v100-straight-blower-duct (Autodesk Fusion 360 design; units mm, degrees)
Autodesk Fusion 360 part; units mm, degrees
sketch "Sketch194" plane through (0, 0, 0) normal (0, 0, 1) x (1, 0, 0)
  line L0 (6.21, -2.88) -> (5.01, -5.52)
  line L1 (5.01, -5.52) -> (2.97, -16.54)
  line L2 (2.97, -16.54) -> (3.01, -81.43)
  line L3 (3.01, -81.43) -> (5.44, -92.47)
  line L4 (5.44, -92.47) -> (7.01, -95.15)
  line L5 (7.01, -95.15) -> (10.23, -96.74)
  line L6 (10.23, -96.74) -> (25.5, -96.54)
  line L7 (25.5, -96.54) -> (30.03, -93.08)
  line L8 (30.03, -93.08) -> (35.46, -92.81)
  line L9 (35.46, -92.81) -> (36.19, -92.08)
  line L10 (36.19, -92.08) -> (36.46, -90.79)
  line L11 (36.46, -90.79) -> (36.46, -41.42)
  line L12 (36.46, -41.42) -> (36.19, -40.42)
  line L13 (36.19, -40.42) -> (35.46, -39.68)
  line L14 (35.46, -39.68) -> (34.46, -39.42)
  line L15 (34.46, -39.42) -> (23.59, -39.42)
  line L16 (23.59, -39.42) -> (23.59, -19.42)
  line L17 (23.59, -19.42) -> (31.82, -19.22)
  line L18 (31.82, -19.22) -> (32.12, -16.44)
  line L19 (32.12, -16.44) -> (31.86, -6.46)
  line L20 (31.86, -6.46) -> (24.9, -0.57)
  line L21 (24.9, -0.57) -> (9.15, -0.57)
  line L22 (9.15, -0.57) -> (6.21, -2.88)
extrude "Extrude154" add sketch "Sketch194" along normal blind 3 makes body 1
ref_plane "WorkPlane174" through (0, 0, 3) normal (0, 0, 1) x (1, 0, 0)
sketch "Sketch195" plane through (0, 0, 3) normal (0, 0, 1) x (1, 0, 0)
  line L0 (6.78, -93) -> (28.42, -93)
  line L1 (28.42, -93) -> (28.42, -4.34)
  line L2 (28.42, -4.34) -> (6.78, -4.34)
  line L3 (6.78, -4.34) -> (6.78, -93)
ref_plane "WorkPlane175" through (0, 0, 20) normal (0, 0, 1) x (1, 0, 0)
sketch "Sketch196" plane through (0, 0, 20) normal (0, 0, 1) x (1, 0, 0)
  line L0 (4.3, -102.1) -> (29.9, -102.1)
  line L1 (29.9, -102.1) -> (29.9, 5.5)
  line L2 (29.9, 5.5) -> (4.3, 5.5)
  line L3 (4.3, 5.5) -> (4.3, -102.1)
loft "Loft21" add profiles "Sketch195", "Sketch196" section 1 section 2 separate body makes body 2
ref_plane "WorkPlane176" through (0, 0, 20) normal (0, 0, 1) x (1, 0, 0)
sketch "Sketch197" plane through (0, 0, 20) normal (0, 0, 1) x (1, 0, 0)
  line L0 (0, -104.4) -> (34.2, -104.4)
  line L1 (34.2, -104.4) -> (34.2, 6)
  line L2 (34.2, 6) -> (0, 6)
  line L3 (0, 6) -> (0, -104.4)
extrude "Extrude155" add sketch "Sketch197" along normal blind 9.8 separate body makes body 3
ref_plane "WorkPlane177" through (0, 0, -6) normal (0, 0, 1) x (1, 0, 0)
sketch "Sketch198" plane through (0, 0, -6) normal (0, 0, 1) x (1, 0, 0)
  line L0 (9.17, -5.2) -> (8.5, -6.63)
  line L1 (8.5, -6.63) -> (6.59, -16.86)
  line L2 (6.59, -16.86) -> (6.64, -81.03)
  line L3 (6.64, -81.03) -> (8.88, -91.12)
  line L4 (8.88, -91.12) -> (9.6, -92.36)
  line L5 (9.6, -92.36) -> (11.08, -93.08)
  line L6 (11.08, -93.08) -> (24.09, -93.08)
  line L7 (24.09, -93.08) -> (28.59, -89.74)
  line L8 (28.59, -89.74) -> (28.59, -39.42)
  line L9 (28.59, -39.42) -> (23.59, -39.42)
  line L10 (23.59, -39.42) -> (23.59, -19.42)
  line L11 (23.59, -19.42) -> (28.59, -19.42)
  line L12 (28.59, -19.42) -> (28.59, -8.35)
  line L13 (28.59, -8.35) -> (23.59, -4.2)
  line L14 (23.59, -4.2) -> (10.42, -4.2)
  line L15 (10.42, -4.2) -> (9.17, -5.2)
extrude "Extrude156" add sketch "Sketch198" along normal blind 6.01 separate body makes body 4
combine "Combine43" operation add target body 1 tool bodies 2 3 4
ref_plane "WorkPlane178" through (0, 0, -7) normal (0, 0, 1) x (1, 0, 0)
sketch "Sketch199" plane through (0, 0, -7) normal (0, 0, 1) x (1, 0, 0)
  line L0 (11.12, -6.2) -> (23.05, -6.14)
  line L1 (23.05, -6.14) -> (26.62, -9.41)
  line L2 (26.62, -9.41) -> (26.59, -17.42)
  line L3 (26.59, -17.42) -> (21.59, -17.42)
  line L4 (21.59, -17.42) -> (21.59, -41.41)
  line L5 (21.59, -41.41) -> (26.59, -41.42)
  line L6 (26.59, -41.42) -> (26.59, -88.69)
  line L7 (26.59, -88.69) -> (23.54, -91.2)
  line L8 (23.54, -91.2) -> (11.58, -91.11)
  line L9 (11.58, -91.11) -> (11, -90.79)
  line L10 (11, -90.79) -> (8.61, -80.54)
  line L11 (8.61, -80.54) -> (8.58, -17.04)
  line L12 (8.58, -17.04) -> (10.26, -7.67)
  line L13 (10.26, -7.67) -> (11.12, -6.2)
extrude "Extrude157" add sketch "Sketch199" along normal blind 10 separate body makes body 5
ref_plane "WorkPlane179" through (0, 0, 2.99) normal (0, 0, 1) x (1, 0, 0)
sketch "Sketch200" plane through (0, 0, 2.99) normal (0, 0, 1) x (1, 0, 0)
  line L0 (8.58, -91.2) -> (26.62, -91.2)
  line L1 (26.62, -91.2) -> (26.62, -6.14)
  line L2 (26.62, -6.14) -> (8.58, -6.14)
  line L3 (8.58, -6.14) -> (8.58, -91.2)
extrude "Extrude158" add sketch "Sketch200" along normal blind 0.02 separate body makes body 6
combine "Combine44" operation add target body 5 tool bodies 6
ref_plane "WorkPlane180" through (0, 0, 3) normal (0, 0, 1) x (1, 0, 0)
sketch "Sketch201" plane through (0, 0, 3) normal (0, 0, 1) x (1, 0, 0)
  line L0 (8.58, -91.2) -> (26.62, -91.2)
  line L1 (26.62, -91.2) -> (26.62, -6.14)
  line L2 (26.62, -6.14) -> (8.58, -6.14)
  line L3 (8.58, -6.14) -> (8.58, -91.2)
ref_plane "WorkPlane181" through (0, 0, 20) normal (0, 0, 1) x (1, 0, 0)
sketch "Sketch202" plane through (0, 0, 20) normal (0, 0, 1) x (1, 0, 0)
  line L0 (6.1, -100.3) -> (28.1, -100.3)
  line L1 (28.1, -100.3) -> (28.1, 3.7)
  line L2 (28.1, 3.7) -> (6.1, 3.7)
  line L3 (6.1, 3.7) -> (6.1, -100.3)
loft "Loft22" add profiles "Sketch201", "Sketch202" section 1 section 2 separate body makes body 7
ref_plane "WorkPlane182" through (0, 0, 19.99) normal (0, 0, 1) x (1, 0, 0)
sketch "Sketch203" plane through (0, 0, 19.99) normal (0, 0, 1) x (1, 0, 0)
  line L0 (6.1, -100.3) -> (28.1, -100.3)
  line L1 (28.1, -100.3) -> (28.1, 3.7)
  line L2 (28.1, 3.7) -> (6.1, 3.7)
  line L3 (6.1, 3.7) -> (6.1, -100.3)
extrude "Extrude159" add sketch "Sketch203" along normal blind 1.82 separate body makes body 8
combine "Combine45" operation add target body 5 tool bodies 7 8
sketch "Sketch204" plane through (0, 0, 0) normal (0, 0, 1) x (1, 0, 0)
  line L0 (21.79, -43.22) -> (80, -43.22)
  line L1 (80, -43.22) -> (80, -15.62)
  line L2 (80, -15.62) -> (21.79, -15.62)
  line L3 (21.79, -15.62) -> (21.79, -43.22)
extrude "Extrude160" add sketch "Sketch204" along normal blind 21.8 separate body makes body 9
ref_plane "WorkPlane183" through (0, 0, 3) normal (0, 0, 1) x (1, 0, 0)
sketch "Sketch205" plane through (0, 0, 3) normal (0, 0, 1) x (1, 0, 0)
  circle A0 centre (31, -52.6) radius 3.7
extrude "Extrude161" add sketch "Sketch205" along normal blind 17 separate body makes body 10
ref_plane "WorkPlane184" through (0, 0, 3) normal (0, 0, 1) x (1, 0, 0)
sketch "Sketch206" plane through (0, 0, 3) normal (0, 0, 1) x (1, 0, 0)
  circle A0 centre (31, -70.36) radius 3.7
extrude "Extrude162" add sketch "Sketch206" along normal blind 17 separate body makes body 11
ref_plane "WorkPlane185" through (0, 0, 3) normal (0, 0, 1) x (1, 0, 0)
sketch "Sketch207" plane through (0, 0, 3) normal (0, 0, 1) x (1, 0, 0)
  circle A0 centre (31, -88.19) radius 3.7
extrude "Extrude163" add sketch "Sketch207" along normal blind 17 separate body makes body 12
combine "Combine46" operation cut target body 5 tool bodies 9 10 11 12
sketch "Sketch208" plane through (0, 0, 0) normal (0, 1, 0) x (1, 0, 0)
  line L0 (32.4, -21.8) -> (32.25, -22.4)
  line L1 (32.25, -22.4) -> (31.7, -22.9)
  line L2 (31.7, -22.9) -> (31.3, -23.3)
  line L3 (31.3, -23.3) -> (31, -23.7)
  line L4 (31, -23.7) -> (30.65, -24.1)
  line L5 (30.65, -24.1) -> (30.55, -24.4)
  line L6 (30.55, -24.4) -> (30.1, -25.4)
  line L7 (30.1, -25.4) -> (29.95, -26.5)
  line L8 (29.95, -26.5) -> (29.95, -27.3)
  line L9 (29.95, -27.3) -> (30.55, -27.3)
  line L10 (30.55, -27.3) -> (30.55, -30.8)
  line L11 (30.55, -30.8) -> (3.65, -30.8)
  line L12 (3.65, -30.8) -> (3.65, -27.3)
  line L13 (3.65, -27.3) -> (4.25, -27.3)
  line L14 (4.25, -27.3) -> (4.25, -26.5)
  line L15 (4.25, -26.5) -> (4.1, -25.4)
  line L16 (4.1, -25.4) -> (3.65, -24.4)
  line L17 (3.65, -24.4) -> (3.55, -24.1)
  line L18 (3.55, -24.1) -> (3.2, -23.7)
  line L19 (3.2, -23.7) -> (2.9, -23.3)
  line L20 (2.9, -23.3) -> (2.5, -22.9)
  line L21 (2.5, -22.9) -> (1.95, -22.4)
  line L22 (1.95, -22.4) -> (1.8, -21.8)
  line L23 (1.8, -21.8) -> (32.4, -21.8)
extrude "Extrude164" add sketch "Sketch208" along normal mid plane 400 separate body makes body 13
ref_plane "WorkPlane186" through (0, 0, 20.8) normal (0, 0, 1) x (1, 0, 0)
sketch "Sketch209" plane through (0, 0, 20.8) normal (0, 0, 1) x (1, 0, 0)
  line L0 (0.8, -102.6) -> (33.4, -102.6)
  line L1 (33.4, -102.6) -> (33.4, 26)
  line L2 (33.4, 26) -> (0.8, 26)
  line L3 (0.8, 26) -> (0.8, -102.6)
extrude "Extrude165" add sketch "Sketch209" along normal blind 11 separate body makes body 14
combine "Combine47" operation intersect target body 13 tool bodies 14
ref_plane "WorkPlane187" through (0, 0, 26.5) normal (0, 0, 1) x (1, 0, 0)
sketch "Sketch210" plane through (0, 0, 26.5) normal (0, 0, 1) x (1, 0, 0)
  line L0 (1.8, -105.4) -> (32.4, -105.4)
  line L1 (32.4, -105.4) -> (32.4, -102.59)
  line L2 (32.4, -102.59) -> (1.8, -102.59)
  line L3 (1.8, -102.59) -> (1.8, -105.4)
extrude "Extrude166" add sketch "Sketch210" along normal blind 4.3 separate body makes body 15
sketch "Sketch211" plane through (0, 0, 0) normal (0, 0, 1) x (1, 0, 0)
  line L0 (23.59, -41.42) -> (80, -41.42)
  line L1 (80, -41.42) -> (80, -17.42)
  line L2 (80, -17.42) -> (23.59, -17.42)
  line L3 (23.59, -17.42) -> (23.59, -41.42)
extrude "Extrude167" add sketch "Sketch211" along normal blind 20 separate body makes body 16
sketch "Sketch212" plane through (0, 0, 0) normal (0, 1, 0) x (1, 0, 0)
  line L0 (32.4, -19.99) -> (72.4, -19.99)
  line L1 (72.4, -19.99) -> (72.4, -60)
  line L2 (72.4, -60) -> (32.4, -19.99)
extrude "Extrude168" add sketch "Sketch212" along normal mid plane 400 separate body makes body 17
ref_plane "WorkPlane188" through (0, 0, 18.99) normal (0, 0, 1) x (1, 0, 0)
sketch "Sketch213" plane through (0, 0, 18.99) normal (0, 0, 1) x (1, 0, 0)
  line L0 (31.4, -41.42) -> (73.4, -41.42)
  line L1 (73.4, -41.42) -> (73.4, -17.42)
  line L2 (73.4, -17.42) -> (31.4, -17.42)
  line L3 (31.4, -17.42) -> (31.4, -41.42)
extrude "Extrude169" add sketch "Sketch213" along normal blind 42.01 separate body makes body 18
combine "Combine48" operation intersect target body 17 tool bodies 18
ref_plane "WorkPlane189" through (0, 0, 3) normal (0, 0, 1) x (1, 0, 0)
sketch "Sketch214" plane through (0, 0, 3) normal (0, 0, 1) x (1, 0, 0)
  circle A0 centre (31, -52.6) radius 2.9
extrude "Extrude170" add sketch "Sketch214" along normal blind 27.8 separate body makes body 19
ref_plane "WorkPlane190" through (0, 0, 3) normal (0, 0, 1) x (1, 0, 0)
sketch "Sketch215" plane through (0, 0, 3) normal (0, 0, 1) x (1, 0, 0)
  circle A0 centre (31, -70.36) radius 2.9
extrude "Extrude171" add sketch "Sketch215" along normal blind 27.8 separate body makes body 20
ref_plane "WorkPlane191" through (0, 0, 3) normal (0, 0, 1) x (1, 0, 0)
sketch "Sketch216" plane through (0, 0, 3) normal (0, 0, 1) x (1, 0, 0)
  circle A0 centre (31, -88.19) radius 2.9
extrude "Extrude172" add sketch "Sketch216" along normal blind 27.8 separate body makes body 21
ref_plane "WorkPlane192" through (0, 0, -1) normal (0, 0, 1) x (1, 0, 0)
sketch "Sketch217" plane through (0, 0, -1) normal (0, 0, 1) x (1, 0, 0)
  circle A0 centre (31, -52.6) radius 2
extrude "Extrude173" add sketch "Sketch217" along normal blind 4.5 separate body makes body 22
ref_plane "WorkPlane193" through (0, 0, -1) normal (0, 0, 1) x (1, 0, 0)
sketch "Sketch218" plane through (0, 0, -1) normal (0, 0, 1) x (1, 0, 0)
  circle A0 centre (31, -70.36) radius 2
extrude "Extrude174" add sketch "Sketch218" along normal blind 4.5 separate body makes body 23
ref_plane "WorkPlane194" through (0, 0, -1) normal (0, 0, 1) x (1, 0, 0)
sketch "Sketch219" plane through (0, 0, -1) normal (0, 0, 1) x (1, 0, 0)
  circle A0 centre (31, -88.19) radius 2
extrude "Extrude175" add sketch "Sketch219" along normal blind 4.5 separate body makes body 24
combine "Combine49" operation cut target body 1 tool bodies 5 13 15 16 17 19 20 21 22 23 24
move_body "Move7" bodies 1 to x (1, 0, 0) y (0, 0, 1) z (0, -1, 0) at (0, 0, 0)
move_body "Move8" bodies 1 to x (1, 0, 0) y (0, 1, 0) z (0, 0, 1) at (-18.23, 11.9, 104.4)
equation "shroud_u = 36.0 mm" comment "fusion_build_duct.py C[]"
equation "shroud_v = 96.6 mm" comment "fusion_build_duct.py C[]"
equation "fin_u0 = 4.5 mm" comment "fusion_build_duct.py C[]"
equation "fin_u1 = 28.1 mm" comment "fusion_build_duct.py C[]"
equation "fin_v0 = 3.2 mm" comment "fusion_build_duct.py C[]"
equation "fin_v1 = 93.4 mm" comment "fusion_build_duct.py C[]"
equation "hole_u = 31.0 mm" comment "fusion_build_duct.py C[]"
equation "plug_u0 = 23.59 mm" comment "fusion_build_duct.py C[]"
equation "plug_v0 = 19.42 mm" comment "fusion_build_duct.py C[]"
equation "plug_v1 = 39.42 mm" comment "fusion_build_duct.py C[]"
equation "plug_z = 28.0 mm" comment "fusion_build_duct.py C[]"
equation "flare_u = 30.0 mm" comment "fusion_build_duct.py C[]"
equation "flare_v = 108.0 mm" comment "fusion_build_duct.py C[]"
equation "flare_d = 4.0 mm" comment "fusion_build_duct.py C[]"
equation "body_u = 25.0 mm" comment "fusion_build_duct.py C[]"
equation "mouth_u = 22.0 mm" comment "fusion_build_duct.py C[]"
equation "mouth_v = 104.0 mm" comment "fusion_build_duct.py C[]"
equation "rib_h = 13.15 mm" comment "fusion_build_duct.py C[]"
equation "rib_d = 5.5 mm" comment "fusion_build_duct.py C[]"
equation "slot_h = 8.0 mm" comment "fusion_build_duct.py C[]"
equation "fan_cu = 17.1 mm" comment "fusion_build_duct.py C[]"
equation "fan_cv = 48.3 mm" comment "fusion_build_duct.py C[]"
equation "fit = 0.3 mm" comment "fusion_build_duct.py C[]"
equation "lip_t = 2.0 mm" comment "fusion_build_duct.py C[]"
equation "nose_d = 6.0 mm" comment "fusion_build_duct.py C[]"
equation "flange_t = 3.0 mm" comment "fusion_build_duct.py C[]"
equation "duct_len = 17.0 mm" comment "fusion_build_duct.py C[]"
equation "wall = 1.8 mm" comment "fusion_build_duct.py C[]"
equation "plug_dv = 2.0 mm" comment "fusion_build_duct.py C[]"
equation "hole_d = 4.0 mm" comment "fusion_build_duct.py C[]"
equation "pocket_d = 5.8 mm" comment "fusion_build_duct.py C[]"
equation "skin = 0.8 mm" comment "fusion_build_duct.py C[]"
named bodies: "duct", "shell", "slot block", "nose", "air", "air flange", "air transition", "air floor", "plug grow", "pocket grow 0", "pocket grow 1", "pocket grow 2", "groove", "groove limit", "peg clearance", "plug", "cable ramp", "cable ramp limit", "pocket 0", "pocket 1", "pocket 2", "hole 0", "hole 1", "hole 2"
